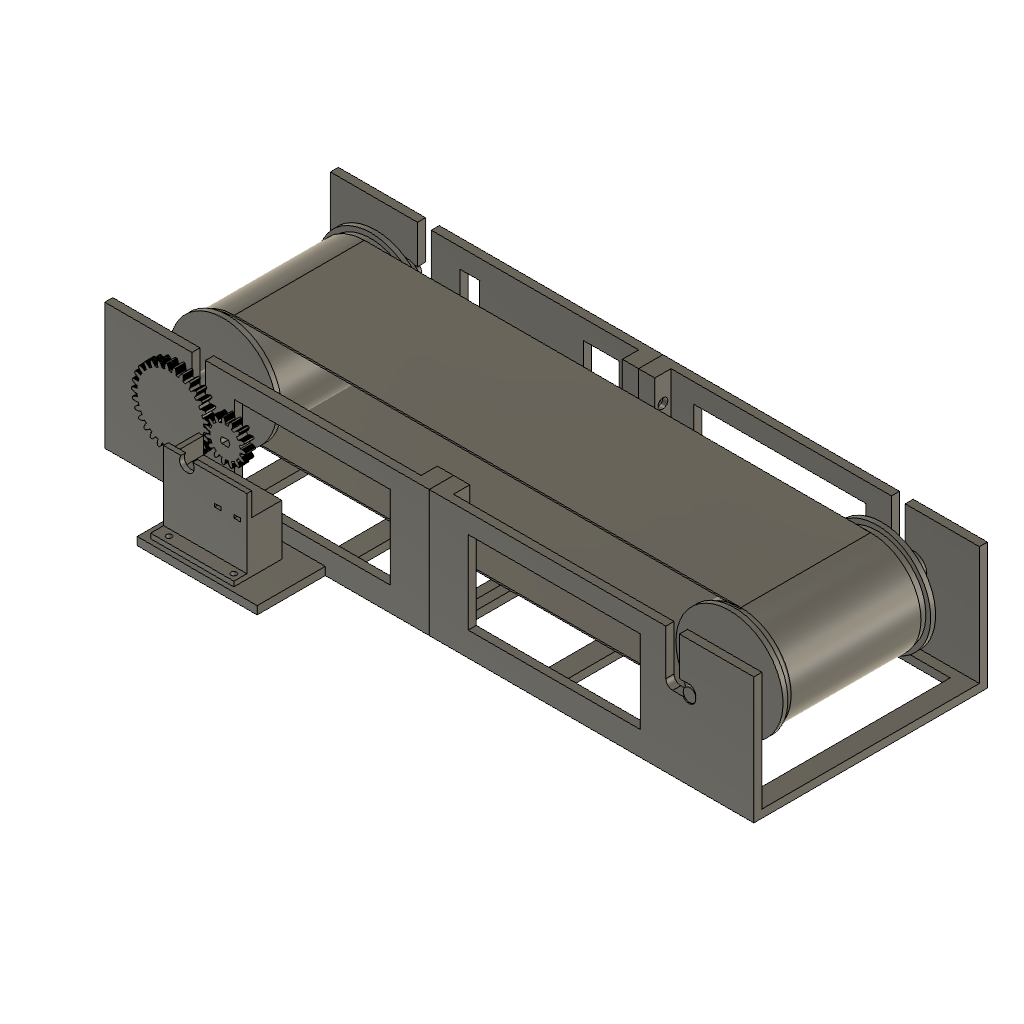
effente_conveyor_2x (Autodesk Fusion 360 design; units mm, degrees)
part number: 2026-11-16-22-43-17-711
part number: 2026-11-16-22-43-17-788
part number: 2026-11-16-22-43-19-483
part number: 2026-11-16-22-43-26-721
part number: 2026-11-16-22-43-27-187
part number: 2026-11-16-22-43-30-080
part number: 2026-11-16-22-43-30-572
Autodesk Fusion 360 part; units mm, degrees
(part 1 of 2)
sketch "Sketch1" plane through (0, 0, 0) normal (0, 0, 1) x (1, 0, 0) in component "Frame"
  line L0 (0, 0) -> (400, 0)
  line L1 (400, 0) -> (400, 144)
  line L2 (400, 144) -> (0, 144)
  line L3 (0, 144) -> (0, 0)
extrude "Extrude1" add sketch "Sketch1" along normal blind 5 makes body 1 in component "Frame"
ref_plane "WorkPlane1" through (0, 0, 5) normal (0, 0, 1) x (1, 0, 0) in component "Frame"
sketch "Sketch2" plane through (0, 0, 5) normal (0, 0, 1) x (1, 0, 0) in component "Frame"
  line L0 (0, 0) -> (400, 0)
  line L1 (400, 0) -> (400, 5)
  line L2 (400, 5) -> (0, 5)
  line L3 (0, 5) -> (0, 0)
extrude "Extrude2" add sketch "Sketch2" along normal blind 73 bodies 1 in component "Frame"
ref_plane "WorkPlane2" through (0, 0, 5) normal (0, 0, 1) x (1, 0, 0) in component "Frame"
sketch "Sketch3" plane through (0, 0, 5) normal (0, 0, 1) x (1, 0, 0) in component "Frame"
  line L0 (0, 139) -> (400, 139)
  line L1 (400, 139) -> (400, 144)
  line L2 (400, 144) -> (0, 144)
  line L3 (0, 144) -> (0, 139)
extrude "Extrude3" add sketch "Sketch3" along normal blind 73 bodies 1 in component "Frame"
sketch "Sketch4" plane through (0, 0, 0) normal (0, 0, 1) x (1, 0, 0) in component "Frame"
  line L0 (62, -42) -> (136, -42)
  line L1 (136, -42) -> (136, 0.5)
  line L2 (136, 0.5) -> (62, 0.5)
  line L3 (62, 0.5) -> (62, -42)
extrude "Extrude4" add sketch "Sketch4" along normal blind 5 bodies 1 in component "Frame"
ref_plane "WorkPlane3" through (0, 2.5, 0) normal (0, 1, 0) x (0, 0, 1) in component "Frame"
sketch "Sketch5" plane through (0, 2.5, 0) normal (0, 1, 0) x (1, 0, 0) in component "Frame"
  line L0 (80, -15) -> (176, -15)
  line L1 (176, -15) -> (176, -66)
  line L2 (176, -66) -> (80, -66)
  line L3 (80, -66) -> (80, -15)
extrude "Extrude5" cut sketch "Sketch5" along normal mid plane 6 bodies 1 in component "Frame"
ref_plane "WorkPlane4" through (0, 2.5, 0) normal (0, 1, 0) x (0, 0, 1) in component "Frame"
sketch "Sketch6" plane through (0, 2.5, 0) normal (0, 1, 0) x (1, 0, 0) in component "Frame"
  line L0 (224, -15) -> (330, -15)
  line L1 (330, -15) -> (330, -66)
  line L2 (330, -66) -> (224, -66)
  line L3 (224, -66) -> (224, -15)
extrude "Extrude6" cut sketch "Sketch6" along normal mid plane 6 bodies 1 in component "Frame"
ref_plane "WorkPlane5" through (0, 141.5, 0) normal (0, 1, 0) x (0, 0, 1) in component "Frame"
sketch "Sketch7" plane through (0, 141.5, 0) normal (0, 1, 0) x (1, 0, 0) in component "Frame"
  line L0 (80, -15) -> (92, -15)
  line L1 (92, -15) -> (92, -66)
  line L2 (92, -66) -> (80, -66)
  line L3 (80, -66) -> (80, -15)
extrude "Extrude7" cut sketch "Sketch7" along normal mid plane 6 bodies 1 in component "Frame"
ref_plane "WorkPlane6" through (0, 141.5, 0) normal (0, 1, 0) x (0, 0, 1) in component "Frame"
sketch "Sketch8" plane through (0, 141.5, 0) normal (0, 1, 0) x (1, 0, 0) in component "Frame"
  line L0 (156, -15) -> (178, -15)
  line L1 (178, -15) -> (178, -66)
  line L2 (178, -66) -> (156, -66)
  line L3 (156, -66) -> (156, -15)
extrude "Extrude8" cut sketch "Sketch8" along normal mid plane 6 bodies 1 in component "Frame"
ref_plane "WorkPlane7" through (0, 141.5, 0) normal (0, 1, 0) x (0, 0, 1) in component "Frame"
sketch "Sketch9" plane through (0, 141.5, 0) normal (0, 1, 0) x (1, 0, 0) in component "Frame"
  line L0 (224, -15) -> (330, -15)
  line L1 (330, -15) -> (330, -66)
  line L2 (330, -66) -> (224, -66)
  line L3 (224, -66) -> (224, -15)
extrude "Extrude9" cut sketch "Sketch9" along normal mid plane 6 bodies 1 in component "Frame"
ref_plane "WorkPlane8" through (0, 0, -0.5) normal (0, 0, 1) x (1, 0, 0) in component "Frame"
sketch "Sketch10" plane through (0, 0, -0.5) normal (0, 0, 1) x (1, 0, 0) in component "Frame"
  line L0 (12, 11) -> (64.6667, 11)
  line L1 (64.6667, 11) -> (64.6667, 133)
  line L2 (64.6667, 133) -> (12, 133)
  line L3 (12, 133) -> (12, 11)
extrude "Extrude10" cut sketch "Sketch10" along normal blind 6 bodies 1 in component "Frame"
ref_plane "WorkPlane9" through (0, 0, -0.5) normal (0, 0, 1) x (1, 0, 0) in component "Frame"
sketch "Sketch11" plane through (0, 0, -0.5) normal (0, 0, 1) x (1, 0, 0) in component "Frame"
  line L0 (76.6667, 11) -> (129.3333, 11)
  line L1 (129.3333, 11) -> (129.3333, 133)
  line L2 (129.3333, 133) -> (76.6667, 133)
  line L3 (76.6667, 133) -> (76.6667, 11)
extrude "Extrude11" cut sketch "Sketch11" along normal blind 6 bodies 1 in component "Frame"
ref_plane "WorkPlane10" through (0, 0, -0.5) normal (0, 0, 1) x (1, 0, 0) in component "Frame"
sketch "Sketch12" plane through (0, 0, -0.5) normal (0, 0, 1) x (1, 0, 0) in component "Frame"
  line L0 (141.3333, 11) -> (194, 11)
  line L1 (194, 11) -> (194, 133)
  line L2 (194, 133) -> (141.3333, 133)
  line L3 (141.3333, 133) -> (141.3333, 11)
extrude "Extrude12" cut sketch "Sketch12" along normal blind 6 bodies 1 in component "Frame"
ref_plane "WorkPlane11" through (0, 0, -0.5) normal (0, 0, 1) x (1, 0, 0) in component "Frame"
sketch "Sketch13" plane through (0, 0, -0.5) normal (0, 0, 1) x (1, 0, 0) in component "Frame"
  line L0 (206, 11) -> (258.6667, 11)
  line L1 (258.6667, 11) -> (258.6667, 133)
  line L2 (258.6667, 133) -> (206, 133)
  line L3 (206, 133) -> (206, 11)
extrude "Extrude13" cut sketch "Sketch13" along normal blind 6 bodies 1 in component "Frame"
ref_plane "WorkPlane12" through (0, 0, -0.5) normal (0, 0, 1) x (1, 0, 0) in component "Frame"
sketch "Sketch14" plane through (0, 0, -0.5) normal (0, 0, 1) x (1, 0, 0) in component "Frame"
  line L0 (270.6667, 11) -> (323.3333, 11)
  line L1 (323.3333, 11) -> (323.3333, 133)
  line L2 (323.3333, 133) -> (270.6667, 133)
  line L3 (270.6667, 133) -> (270.6667, 11)
extrude "Extrude14" cut sketch "Sketch14" along normal blind 6 bodies 1 in component "Frame"
ref_plane "WorkPlane13" through (0, 0, -0.5) normal (0, 0, 1) x (1, 0, 0) in component "Frame"
sketch "Sketch15" plane through (0, 0, -0.5) normal (0, 0, 1) x (1, 0, 0) in component "Frame"
  line L0 (335.3333, 11) -> (388, 11)
  line L1 (388, 11) -> (388, 133)
  line L2 (388, 133) -> (335.3333, 133)
  line L3 (335.3333, 133) -> (335.3333, 11)
extrude "Extrude15" cut sketch "Sketch15" along normal blind 6 bodies 1 in component "Frame"
sketch "Sketch16" plane through (0, 0, 0) normal (0, 0, 1) x (1, 0, 0) in component "Frame"
  line L0 (190, 4.99) -> (210, 4.99)
  line L1 (210, 4.99) -> (210, 15)
  line L2 (210, 15) -> (190, 15)
  line L3 (190, 15) -> (190, 4.99)
extrude "Extrude16" add sketch "Sketch16" along normal blind 78 bodies 1 in component "Frame"
sketch "Sketch17" plane through (0, 0, 0) normal (0, 0, 1) x (1, 0, 0) in component "Frame"
  line L0 (190, 129) -> (210, 129)
  line L1 (210, 129) -> (210, 139.01)
  line L2 (210, 139.01) -> (190, 139.01)
  line L3 (190, 139.01) -> (190, 129)
extrude "Extrude17" add sketch "Sketch17" along normal blind 78 bodies 1 in component "Frame"
sketch "Sketch18" plane through (0, 0, 0) normal (0, 0, 1) x (1, 0, 0) in component "Frame"
  line L0 (190, 60) -> (210, 60)
  line L1 (210, 60) -> (210, 84)
  line L2 (210, 84) -> (190, 84)
  line L3 (190, 84) -> (190, 60)
extrude "Extrude18" add sketch "Sketch18" along normal blind 13 bodies 1 in component "Frame"
ref_plane "WorkPlane14" through (200, 0, 0) normal (1, 0, 0) x (0, 1, 0) in component "Frame"
sketch "Sketch19" plane through (200, 0, 0) normal (1, 0, 0) x (0, 0, -1) in component "Frame"
  circle A0 centre (-22, 10) radius 1.7
extrude "Extrude19" cut sketch "Sketch19" along normal mid plane 21 bodies 1 in component "Frame"
ref_plane "WorkPlane15" through (191, 0, 0) normal (1, 0, 0) x (0, 1, 0) in component "Frame"
sketch "Sketch20" plane through (191, 0, 0) normal (1, 0, 0) x (0, 0, -1) in component "Frame"
  line L0 (-23.6166, 12.8) -> (-25.2332, 10)
  line L1 (-25.2332, 10) -> (-23.6166, 7.2)
  line L2 (-23.6166, 7.2) -> (-20.3834, 7.2)
  line L3 (-20.3834, 7.2) -> (-18.7668, 10)
  line L4 (-18.7668, 10) -> (-20.3834, 12.8)
  line L5 (-20.3834, 12.8) -> (-23.6166, 12.8)
extrude "Extrude20" cut sketch "Sketch20" along normal mid plane 3 bodies 1 in component "Frame"
ref_plane "WorkPlane16" through (208.75, 0, 0) normal (1, 0, 0) x (0, 1, 0) in component "Frame"
sketch "Sketch21" plane through (208.75, 0, 0) normal (1, 0, 0) x (0, 0, -1) in component "Frame"
  circle A0 centre (-22, 10) radius 3
extrude "Extrude21" cut sketch "Sketch21" along normal mid plane 3.5 bodies 1 in component "Frame"
ref_plane "WorkPlane17" through (200, 0, 0) normal (1, 0, 0) x (0, 1, 0) in component "Frame"
sketch "Sketch22" plane through (200, 0, 0) normal (1, 0, 0) x (0, 0, -1) in component "Frame"
  circle A0 centre (-62, 10) radius 1.7
extrude "Extrude22" cut sketch "Sketch22" along normal mid plane 21 bodies 1 in component "Frame"
ref_plane "WorkPlane18" through (191, 0, 0) normal (1, 0, 0) x (0, 1, 0) in component "Frame"
sketch "Sketch23" plane through (191, 0, 0) normal (1, 0, 0) x (0, 0, -1) in component "Frame"
  line L0 (-63.6166, 12.8) -> (-65.2332, 10)
  line L1 (-65.2332, 10) -> (-63.6166, 7.2)
  line L2 (-63.6166, 7.2) -> (-60.3834, 7.2)
  line L3 (-60.3834, 7.2) -> (-58.7668, 10)
  line L4 (-58.7668, 10) -> (-60.3834, 12.8)
  line L5 (-60.3834, 12.8) -> (-63.6166, 12.8)
extrude "Extrude23" cut sketch "Sketch23" along normal mid plane 3 bodies 1 in component "Frame"
ref_plane "WorkPlane19" through (208.75, 0, 0) normal (1, 0, 0) x (0, 1, 0) in component "Frame"
sketch "Sketch24" plane through (208.75, 0, 0) normal (1, 0, 0) x (0, 0, -1) in component "Frame"
  circle A0 centre (-62, 10) radius 3
extrude "Extrude24" cut sketch "Sketch24" along normal mid plane 3.5 bodies 1 in component "Frame"
ref_plane "WorkPlane20" through (200, 0, 0) normal (1, 0, 0) x (0, 1, 0) in component "Frame"
sketch "Sketch25" plane through (200, 0, 0) normal (1, 0, 0) x (0, 0, -1) in component "Frame"
  circle A0 centre (-22, 134) radius 1.7
extrude "Extrude25" cut sketch "Sketch25" along normal mid plane 21 bodies 1 in component "Frame"
ref_plane "WorkPlane21" through (191, 0, 0) normal (1, 0, 0) x (0, 1, 0) in component "Frame"
sketch "Sketch26" plane through (191, 0, 0) normal (1, 0, 0) x (0, 0, -1) in component "Frame"
  line L0 (-23.6166, 136.8) -> (-25.2332, 134)
  line L1 (-25.2332, 134) -> (-23.6166, 131.2)
  line L2 (-23.6166, 131.2) -> (-20.3834, 131.2)
  line L3 (-20.3834, 131.2) -> (-18.7668, 134)
  line L4 (-18.7668, 134) -> (-20.3834, 136.8)
  line L5 (-20.3834, 136.8) -> (-23.6166, 136.8)
extrude "Extrude26" cut sketch "Sketch26" along normal mid plane 3 bodies 1 in component "Frame"
ref_plane "WorkPlane22" through (208.75, 0, 0) normal (1, 0, 0) x (0, 1, 0) in component "Frame"
sketch "Sketch27" plane through (208.75, 0, 0) normal (1, 0, 0) x (0, 0, -1) in component "Frame"
  circle A0 centre (-22, 134) radius 3
extrude "Extrude27" cut sketch "Sketch27" along normal mid plane 3.5 bodies 1 in component "Frame"
ref_plane "WorkPlane23" through (200, 0, 0) normal (1, 0, 0) x (0, 1, 0) in component "Frame"
sketch "Sketch28" plane through (200, 0, 0) normal (1, 0, 0) x (0, 0, -1) in component "Frame"
  circle A0 centre (-62, 134) radius 1.7
extrude "Extrude28" cut sketch "Sketch28" along normal mid plane 21 bodies 1 in component "Frame"
ref_plane "WorkPlane24" through (191, 0, 0) normal (1, 0, 0) x (0, 1, 0) in component "Frame"
sketch "Sketch29" plane through (191, 0, 0) normal (1, 0, 0) x (0, 0, -1) in component "Frame"
  line L0 (-63.6166, 136.8) -> (-65.2332, 134)
  line L1 (-65.2332, 134) -> (-63.6166, 131.2)
  line L2 (-63.6166, 131.2) -> (-60.3834, 131.2)
  line L3 (-60.3834, 131.2) -> (-58.7668, 134)
  line L4 (-58.7668, 134) -> (-60.3834, 136.8)
  line L5 (-60.3834, 136.8) -> (-63.6166, 136.8)
extrude "Extrude29" cut sketch "Sketch29" along normal mid plane 3 bodies 1 in component "Frame"
ref_plane "WorkPlane25" through (208.75, 0, 0) normal (1, 0, 0) x (0, 1, 0) in component "Frame"
sketch "Sketch30" plane through (208.75, 0, 0) normal (1, 0, 0) x (0, 0, -1) in component "Frame"
  circle A0 centre (-62, 134) radius 3
extrude "Extrude30" cut sketch "Sketch30" along normal mid plane 3.5 bodies 1 in component "Frame"
ref_plane "WorkPlane26" through (200, 0, 0) normal (1, 0, 0) x (0, 1, 0) in component "Frame"
sketch "Sketch31" plane through (200, 0, 0) normal (1, 0, 0) x (0, 0, -1) in component "Frame"
  circle A0 centre (-8, 72) radius 1.7
extrude "Extrude31" cut sketch "Sketch31" along normal mid plane 21 bodies 1 in component "Frame"
ref_plane "WorkPlane27" through (191, 0, 0) normal (1, 0, 0) x (0, 1, 0) in component "Frame"
sketch "Sketch32" plane through (191, 0, 0) normal (1, 0, 0) x (0, 0, -1) in component "Frame"
  line L0 (-9.6166, 74.8) -> (-11.2332, 72)
  line L1 (-11.2332, 72) -> (-9.6166, 69.2)
  line L2 (-9.6166, 69.2) -> (-6.3834, 69.2)
  line L3 (-6.3834, 69.2) -> (-4.7668, 72)
  line L4 (-4.7668, 72) -> (-6.3834, 74.8)
  line L5 (-6.3834, 74.8) -> (-9.6166, 74.8)
extrude "Extrude32" cut sketch "Sketch32" along normal mid plane 3 bodies 1 in component "Frame"
ref_plane "WorkPlane28" through (208.75, 0, 0) normal (1, 0, 0) x (0, 1, 0) in component "Frame"
sketch "Sketch33" plane through (208.75, 0, 0) normal (1, 0, 0) x (0, 0, -1) in component "Frame"
  circle A0 centre (-8, 72) radius 3
extrude "Extrude33" cut sketch "Sketch33" along normal mid plane 3.5 bodies 1 in component "Frame"
ref_plane "WorkPlane29" through (0, 2.5, 0) normal (0, 1, 0) x (0, 0, 1) in component "Frame"
sketch "Sketch34" plane through (0, 2.5, 0) normal (0, 1, 0) x (1, 0, 0) in component "Frame"
  circle A0 centre (48, -48) radius 4.2
extrude "Extrude34" cut sketch "Sketch34" along normal mid plane 6 bodies 1 in component "Frame"
ref_plane "WorkPlane30" through (0, 2.5, 0) normal (0, 1, 0) x (0, 0, 1) in component "Frame"
sketch "Sketch35" plane through (0, 2.5, 0) normal (0, 1, 0) x (1, 0, 0) in component "Frame"
  line L0 (48, -45.8) -> (58, -45.8)
  line L1 (58, -45.8) -> (58, -54.2)
  line L2 (58, -54.2) -> (48, -54.2)
  line L3 (48, -54.2) -> (48, -45.8)
extrude "Extrude35" cut sketch "Sketch35" along normal mid plane 6 bodies 1 in component "Frame"
ref_plane "WorkPlane31" through (0, 2.5, 0) normal (0, 1, 0) x (0, 0, 1) in component "Frame"
sketch "Sketch36" plane through (0, 2.5, 0) normal (0, 1, 0) x (1, 0, 0) in component "Frame"
  circle A0 centre (48, -50) radius 4.2
extrude "Extrude36" cut sketch "Sketch36" along normal mid plane 6 bodies 1 in component "Frame"
ref_plane "WorkPlane32" through (0, 2.5, 0) normal (0, 1, 0) x (0, 0, 1) in component "Frame"
sketch "Sketch37" plane through (0, 2.5, 0) normal (0, 1, 0) x (1, 0, 0) in component "Frame"
  circle A0 centre (58, -50) radius 4.2
extrude "Extrude37" cut sketch "Sketch37" along normal mid plane 6 bodies 1 in component "Frame"
ref_plane "WorkPlane33" through (0, 2.5, 0) normal (0, 1, 0) x (0, 0, 1) in component "Frame"
sketch "Sketch38" plane through (0, 2.5, 0) normal (0, 1, 0) x (1, 0, 0) in component "Frame"
  line L0 (53.8, -50) -> (62.2, -50)
  line L1 (62.2, -50) -> (62.2, -79)
  line L2 (62.2, -79) -> (53.8, -79)
  line L3 (53.8, -79) -> (53.8, -50)
extrude "Extrude38" cut sketch "Sketch38" along normal mid plane 6 bodies 1 in component "Frame"
ref_plane "WorkPlane34" through (0, 141.5, 0) normal (0, 1, 0) x (0, 0, 1) in component "Frame"
sketch "Sketch39" plane through (0, 141.5, 0) normal (0, 1, 0) x (1, 0, 0) in component "Frame"
  circle A0 centre (48, -48) radius 4.2
extrude "Extrude39" cut sketch "Sketch39" along normal mid plane 6 bodies 1 in component "Frame"
ref_plane "WorkPlane35" through (0, 141.5, 0) normal (0, 1, 0) x (0, 0, 1) in component "Frame"
sketch "Sketch40" plane through (0, 141.5, 0) normal (0, 1, 0) x (1, 0, 0) in component "Frame"
  line L0 (48, -45.8) -> (58, -45.8)
  line L1 (58, -45.8) -> (58, -54.2)
  line L2 (58, -54.2) -> (48, -54.2)
  line L3 (48, -54.2) -> (48, -45.8)
extrude "Extrude40" cut sketch "Sketch40" along normal mid plane 6 bodies 1 in component "Frame"
ref_plane "WorkPlane36" through (0, 141.5, 0) normal (0, 1, 0) x (0, 0, 1) in component "Frame"
sketch "Sketch41" plane through (0, 141.5, 0) normal (0, 1, 0) x (1, 0, 0) in component "Frame"
  circle A0 centre (48, -50) radius 4.2
extrude "Extrude41" cut sketch "Sketch41" along normal mid plane 6 bodies 1 in component "Frame"
ref_plane "WorkPlane37" through (0, 141.5, 0) normal (0, 1, 0) x (0, 0, 1) in component "Frame"
sketch "Sketch42" plane through (0, 141.5, 0) normal (0, 1, 0) x (1, 0, 0) in component "Frame"
  circle A0 centre (58, -50) radius 4.2
extrude "Extrude42" cut sketch "Sketch42" along normal mid plane 6 bodies 1 in component "Frame"
ref_plane "WorkPlane38" through (0, 141.5, 0) normal (0, 1, 0) x (0, 0, 1) in component "Frame"
sketch "Sketch43" plane through (0, 141.5, 0) normal (0, 1, 0) x (1, 0, 0) in component "Frame"
  line L0 (53.8, -50) -> (62.2, -50)
  line L1 (62.2, -50) -> (62.2, -79)
  line L2 (62.2, -79) -> (53.8, -79)
  line L3 (53.8, -79) -> (53.8, -50)
extrude "Extrude43" cut sketch "Sketch43" along normal mid plane 6 bodies 1 in component "Frame"
ref_plane "WorkPlane39" through (0, 2.5, 0) normal (0, 1, 0) x (0, 0, 1) in component "Frame"
sketch "Sketch44" plane through (0, 2.5, 0) normal (0, 1, 0) x (1, 0, 0) in component "Frame"
  circle A0 centre (360, -48) radius 4.2
extrude "Extrude44" cut sketch "Sketch44" along normal mid plane 6 bodies 1 in component "Frame"
ref_plane "WorkPlane40" through (0, 2.5, 0) normal (0, 1, 0) x (0, 0, 1) in component "Frame"
sketch "Sketch45" plane through (0, 2.5, 0) normal (0, 1, 0) x (1, 0, 0) in component "Frame"
  line L0 (350, -45.8) -> (360, -45.8)
  line L1 (360, -45.8) -> (360, -54.2)
  line L2 (360, -54.2) -> (350, -54.2)
  line L3 (350, -54.2) -> (350, -45.8)
extrude "Extrude45" cut sketch "Sketch45" along normal mid plane 6 bodies 1 in component "Frame"
ref_plane "WorkPlane41" through (0, 2.5, 0) normal (0, 1, 0) x (0, 0, 1) in component "Frame"
sketch "Sketch46" plane through (0, 2.5, 0) normal (0, 1, 0) x (1, 0, 0) in component "Frame"
  circle A0 centre (360, -50) radius 4.2
extrude "Extrude46" cut sketch "Sketch46" along normal mid plane 6 bodies 1 in component "Frame"
ref_plane "WorkPlane42" through (0, 2.5, 0) normal (0, 1, 0) x (0, 0, 1) in component "Frame"
sketch "Sketch47" plane through (0, 2.5, 0) normal (0, 1, 0) x (1, 0, 0) in component "Frame"
  circle A0 centre (350, -50) radius 4.2
extrude "Extrude47" cut sketch "Sketch47" along normal mid plane 6 bodies 1 in component "Frame"
ref_plane "WorkPlane43" through (0, 2.5, 0) normal (0, 1, 0) x (0, 0, 1) in component "Frame"
sketch "Sketch48" plane through (0, 2.5, 0) normal (0, 1, 0) x (1, 0, 0) in component "Frame"
  line L0 (345.8, -50) -> (354.2, -50)
  line L1 (354.2, -50) -> (354.2, -79)
  line L2 (354.2, -79) -> (345.8, -79)
  line L3 (345.8, -79) -> (345.8, -50)
extrude "Extrude48" cut sketch "Sketch48" along normal mid plane 6 bodies 1 in component "Frame"
ref_plane "WorkPlane44" through (0, 141.5, 0) normal (0, 1, 0) x (0, 0, 1) in component "Frame"
sketch "Sketch49" plane through (0, 141.5, 0) normal (0, 1, 0) x (1, 0, 0) in component "Frame"
  circle A0 centre (360, -48) radius 4.2
extrude "Extrude49" cut sketch "Sketch49" along normal mid plane 6 bodies 1 in component "Frame"
ref_plane "WorkPlane45" through (0, 141.5, 0) normal (0, 1, 0) x (0, 0, 1) in component "Frame"
sketch "Sketch50" plane through (0, 141.5, 0) normal (0, 1, 0) x (1, 0, 0) in component "Frame"
  line L0 (350, -45.8) -> (360, -45.8)
  line L1 (360, -45.8) -> (360, -54.2)
  line L2 (360, -54.2) -> (350, -54.2)
  line L3 (350, -54.2) -> (350, -45.8)
extrude "Extrude50" cut sketch "Sketch50" along normal mid plane 6 bodies 1 in component "Frame"
ref_plane "WorkPlane46" through (0, 141.5, 0) normal (0, 1, 0) x (0, 0, 1) in component "Frame"
sketch "Sketch51" plane through (0, 141.5, 0) normal (0, 1, 0) x (1, 0, 0) in component "Frame"
  circle A0 centre (360, -50) radius 4.2
extrude "Extrude51" cut sketch "Sketch51" along normal mid plane 6 bodies 1 in component "Frame"
ref_plane "WorkPlane47" through (0, 141.5, 0) normal (0, 1, 0) x (0, 0, 1) in component "Frame"
sketch "Sketch52" plane through (0, 141.5, 0) normal (0, 1, 0) x (1, 0, 0) in component "Frame"
  circle A0 centre (350, -50) radius 4.2
extrude "Extrude52" cut sketch "Sketch52" along normal mid plane 6 bodies 1 in component "Frame"
ref_plane "WorkPlane48" through (0, 141.5, 0) normal (0, 1, 0) x (0, 0, 1) in component "Frame"
sketch "Sketch53" plane through (0, 141.5, 0) normal (0, 1, 0) x (1, 0, 0) in component "Frame"
  line L0 (345.8, -50) -> (354.2, -50)
  line L1 (354.2, -50) -> (354.2, -79)
  line L2 (354.2, -79) -> (345.8, -79)
  line L3 (345.8, -79) -> (345.8, -50)
extrude "Extrude53" cut sketch "Sketch53" along normal mid plane 6 bodies 1 in component "Frame"
ref_plane "WorkPlane49" through (0, 0, -0.5) normal (0, 0, 1) x (1, 0, 0) in component "Frame"
sketch "Sketch54" plane through (0, 0, -0.5) normal (0, 0, 1) x (1, 0, 0) in component "Frame"
  circle A0 centre (74.75, -35.1) radius 1.7
extrude "Extrude54" cut sketch "Sketch54" along normal blind 6 bodies 1 in component "Frame"
ref_plane "WorkPlane50" through (0, 0, -0.5) normal (0, 0, 1) x (1, 0, 0) in component "Frame"
sketch "Sketch55" plane through (0, 0, -0.5) normal (0, 0, 1) x (1, 0, 0) in component "Frame"
  line L0 (77.9832, -35.1) -> (76.3666, -32.3)
  line L1 (76.3666, -32.3) -> (73.1334, -32.3)
  line L2 (73.1334, -32.3) -> (71.5168, -35.1)
  line L3 (71.5168, -35.1) -> (73.1334, -37.9)
  line L4 (73.1334, -37.9) -> (76.3666, -37.9)
  line L5 (76.3666, -37.9) -> (77.9832, -35.1)
extrude "Extrude55" cut sketch "Sketch55" along normal blind 3 bodies 1 in component "Frame"
ref_plane "WorkPlane51" through (0, 0, -0.5) normal (0, 0, 1) x (1, 0, 0) in component "Frame"
sketch "Sketch56" plane through (0, 0, -0.5) normal (0, 0, 1) x (1, 0, 0) in component "Frame"
  circle A0 centre (114.75, -35.1) radius 1.7
extrude "Extrude56" cut sketch "Sketch56" along normal blind 6 bodies 1 in component "Frame"
ref_plane "WorkPlane52" through (0, 0, -0.5) normal (0, 0, 1) x (1, 0, 0) in component "Frame"
sketch "Sketch57" plane through (0, 0, -0.5) normal (0, 0, 1) x (1, 0, 0) in component "Frame"
  line L0 (117.9832, -35.1) -> (116.3666, -32.3)
  line L1 (116.3666, -32.3) -> (113.1334, -32.3)
  line L2 (113.1334, -32.3) -> (111.5168, -35.1)
  line L3 (111.5168, -35.1) -> (113.1334, -37.9)
  line L4 (113.1334, -37.9) -> (116.3666, -37.9)
  line L5 (116.3666, -37.9) -> (117.9832, -35.1)
extrude "Extrude57" cut sketch "Sketch57" along normal blind 3 bodies 1 in component "Frame"
ref_plane "WorkPlane53" through (0, 143.25, 0) normal (0, 1, 0) x (0, 0, 1) in component "Frame"
sketch "Sketch58" plane through (0, 143.25, 0) normal (0, 1, 0) x (1, 0, 0) in component "Frame"
  circle A0 centre (120, -48) radius 10.05
extrude "Extrude58" cut sketch "Sketch58" along normal mid plane 2.5 bodies 1 in component "Frame"
ref_plane "WorkPlane54" through (200, 0, 0) normal (1, 0, 0) x (0, 1, 0) in component "Frame"
split "Split1" by plane through (200, 0, 0) normal (1, 0, 0) bodies 1 makes body 2 at (388.0369, 0, 41.7129) in component "Frame"
ref_plane "WorkPlane1" through (0, 72, 0) normal (0, 1, 0) x (0, 0, 1) in component "Drive roller"
sketch "Sketch1 (2)" plane through (0, 72, 0) normal (0, 1, 0) x (1, 0, 0) in component "Drive roller"
  circle A0 centre (48, -48) radius 30
extrude "Extrude1'" add sketch "Sketch1 (2)" along normal mid plane 88 separate body makes body 3 in component "Drive roller"
ref_plane "WorkPlane2" through (0, 26.5, 0) normal (0, 1, 0) x (0, 0, 1) in component "Drive roller"
sketch "Sketch2 (2)" plane through (0, 26.5, 0) normal (0, 1, 0) x (1, 0, 0) in component "Drive roller"
  circle A0 centre (48, -48) radius 33
extrude "Extrude2'" add sketch "Sketch2 (2)" along normal mid plane 3 bodies 3 in component "Drive roller"
ref_plane "WorkPlane3" through (0, 117.5, 0) normal (0, 1, 0) x (0, 0, 1) in component "Drive roller"
sketch "Sketch3 (2)" plane through (0, 117.5, 0) normal (0, 1, 0) x (1, 0, 0) in component "Drive roller"
  circle A0 centre (48, -48) radius 33
extrude "Extrude3'" add sketch "Sketch3 (2)" along normal mid plane 3 bodies 3 in component "Drive roller"
ref_plane "WorkPlane4" through (0, 128.75, 0) normal (0, 1, 0) x (0, 0, 1) in component "Drive roller"
sketch "Sketch4 (2)" plane through (0, 128.75, 0) normal (0, 1, 0) x (1, 0, 0) in component "Drive roller"
  circle A0 centre (48, -48) radius 8
extrude "Extrude4'" add sketch "Sketch4 (2)" along normal mid plane 19.5 bodies 3 in component "Drive roller"
ref_plane "WorkPlane5" through (0, 141, 0) normal (0, 1, 0) x (0, 0, 1) in component "Drive roller"
sketch "Sketch5 (2)" plane through (0, 141, 0) normal (0, 1, 0) x (1, 0, 0) in component "Drive roller"
  circle A0 centre (48, -48) radius 4
extrude "Extrude5'" add sketch "Sketch5 (2)" along normal mid plane 5 bodies 3 in component "Drive roller"
ref_plane "WorkPlane6" through (0, 15.25, 0) normal (0, 1, 0) x (0, 0, 1) in component "Drive roller"
sketch "Sketch6 (2)" plane through (0, 15.25, 0) normal (0, 1, 0) x (1, 0, 0) in component "Drive roller"
  circle A0 centre (48, -48) radius 8
extrude "Extrude6'" add sketch "Sketch6 (2)" along normal mid plane 19.5 bodies 3 in component "Drive roller"
ref_plane "WorkPlane7" through (0, 1.995, 0) normal (0, 1, 0) x (0, 0, 1) in component "Drive roller"
sketch "Sketch7 (2)" plane through (0, 1.995, 0) normal (0, 1, 0) x (1, 0, 0) in component "Drive roller"
  circle A0 centre (48, -48) radius 4
extrude "Extrude7'" add sketch "Sketch7 (2)" along normal mid plane 7.01 bodies 3 in component "Drive roller"
ref_plane "WorkPlane8" through (0, -4.5, 0) normal (0, 1, 0) x (0, 0, 1) in component "Drive roller"
sketch "Sketch8 (2)" plane through (0, -4.5, 0) normal (0, 1, 0) x (1, 0, 0) in component "Drive roller"
  line L0 (68.5814, -46.6595) -> (69.0984, -46.6258)
  line L1 (69.0984, -46.6258) -> (69.4576, -46.6466)
  line L2 (69.4576, -46.6466) -> (69.8189, -46.7052)
  line L3 (69.8189, -46.7052) -> (70.1814, -46.7894)
  line L4 (70.1814, -46.7894) -> (70.5445, -46.8952)
  line L5 (70.5445, -46.8952) -> (70.9077, -47.0204)
  line L6 (70.9077, -47.0204) -> (71.2707, -47.1637)
  line L7 (71.2707, -47.1637) -> (71.6332, -47.3239)
  line L8 (71.6332, -47.3239) -> (71.9948, -47.5003)
  line L9 (71.9948, -47.5003) -> (71.9948, -48.4997)
  line L10 (71.9948, -48.4997) -> (71.6332, -48.6761)
  line L11 (71.6332, -48.6761) -> (71.2707, -48.8363)
  line L12 (71.2707, -48.8363) -> (70.9077, -48.9796)
  line L13 (70.9077, -48.9796) -> (70.5445, -49.1048)
  line L14 (70.5445, -49.1048) -> (70.1814, -49.2106)
  line L15 (70.1814, -49.2106) -> (69.8189, -49.2948)
  line L16 (69.8189, -49.2948) -> (69.4576, -49.3534)
  line L17 (69.4576, -49.3534) -> (69.0984, -49.3742)
  line L18 (69.0984, -49.3742) -> (68.5814, -49.3405)
  line L19 (68.5814, -49.3405) -> (68.4104, -50.9679)
  line L20 (68.4104, -50.9679) -> (68.923, -51.0424)
  line L21 (68.923, -51.0424) -> (69.27, -51.1375)
  line L22 (69.27, -51.1375) -> (69.6113, -51.2699)
  line L23 (69.6113, -51.2699) -> (69.9484, -51.4276)
  line L24 (69.9484, -51.4276) -> (70.2815, -51.6066)
  line L25 (70.2815, -51.6066) -> (70.6108, -51.8046)
  line L26 (70.6108, -51.8046) -> (70.9361, -52.0202)
  line L27 (70.9361, -52.0202) -> (71.2573, -52.2523)
  line L28 (71.2573, -52.2523) -> (71.5743, -52.5)
  line L29 (71.5743, -52.5) -> (71.3666, -53.4776)
  line L30 (71.3666, -53.4776) -> (70.9762, -53.575)
  line L31 (70.9762, -53.575) -> (70.5883, -53.6563)
  line L32 (70.5883, -53.6563) -> (70.2035, -53.7209)
  line L33 (70.2035, -53.7209) -> (69.8221, -53.7679)
  line L34 (69.8221, -53.7679) -> (69.445, -53.796)
  line L35 (69.445, -53.796) -> (69.0729, -53.803)
  line L36 (69.0729, -53.803) -> (68.7073, -53.7851)
  line L37 (68.7073, -53.7851) -> (68.3516, -53.7308)
  line L38 (68.3516, -53.7308) -> (67.8529, -53.5904)
  line L39 (67.8529, -53.5904) -> (67.3473, -55.1466)
  line L40 (67.3473, -55.1466) -> (67.8333, -55.3261)
  line L41 (67.8333, -55.3261) -> (68.1529, -55.4912)
  line L42 (68.1529, -55.4912) -> (68.4592, -55.6917)
  line L43 (68.4592, -55.6917) -> (68.7561, -55.916)
  line L44 (68.7561, -55.916) -> (69.0448, -56.1604)
  line L45 (69.0448, -56.1604) -> (69.3257, -56.4225)
  line L46 (69.3257, -56.4225) -> (69.599, -56.701)
  line L47 (69.599, -56.701) -> (69.865, -56.9948)
  line L48 (69.865, -56.9948) -> (70.1236, -57.3031)
  line L49 (70.1236, -57.3031) -> (69.7171, -58.216)
  line L50 (69.7171, -58.216) -> (69.315, -58.2302)
  line L51 (69.315, -58.2302) -> (68.9187, -58.2291)
  line L52 (68.9187, -58.2291) -> (68.5288, -58.2123)
  line L53 (68.5288, -58.2123) -> (68.146, -58.179)
  line L54 (68.146, -58.179) -> (67.7713, -58.128)
  line L55 (67.7713, -58.128) -> (67.4059, -58.0575)
  line L56 (67.4059, -58.0575) -> (67.052, -57.9639)
  line L57 (67.052, -57.9639) -> (66.7154, -57.8369)
  line L58 (66.7154, -57.8369) -> (66.2568, -57.5959)
  line L59 (66.2568, -57.5959) -> (65.4386, -59.0129)
  line L60 (65.4386, -59.0129) -> (65.8767, -59.2895)
  line L61 (65.8767, -59.2895) -> (66.155, -59.5175)
  line L62 (66.155, -59.5175) -> (66.413, -59.7773)
  line L63 (66.413, -59.7773) -> (66.6567, -60.0585)
  line L64 (66.6567, -60.0585) -> (66.8883, -60.3575)
  line L65 (66.8883, -60.3575) -> (67.1085, -60.6723)
  line L66 (67.1085, -60.6723) -> (67.318, -61.0016)
  line L67 (67.318, -61.0016) -> (67.5171, -61.3443)
  line L68 (67.5171, -61.3443) -> (67.7059, -61.6995)
  line L69 (67.7059, -61.6995) -> (67.1185, -62.508)
  line L70 (67.1185, -62.508) -> (66.7223, -62.4382)
  line L71 (66.7223, -62.4382) -> (66.3349, -62.3548)
  line L72 (66.3349, -62.3548) -> (65.957, -62.2573)
  line L73 (65.957, -62.2573) -> (65.5895, -62.1451)
  line L74 (65.5895, -62.1451) -> (65.2335, -62.0173)
  line L75 (65.2335, -62.0173) -> (64.8908, -61.8724)
  line L76 (64.8908, -61.8724) -> (64.564, -61.7073)
  line L77 (64.564, -61.7073) -> (64.2612, -61.5131)
  line L78 (64.2612, -61.5131) -> (63.8627, -61.182)
  line L79 (63.8627, -61.182) -> (62.7679, -62.398)
  line L80 (62.7679, -62.398) -> (63.1388, -62.7596)
  line L81 (63.1388, -62.7596) -> (63.3637, -63.0405)
  line L82 (63.3637, -63.0405) -> (63.562, -63.3482)
  line L83 (63.562, -63.3482) -> (63.7419, -63.6739)
  line L84 (63.7419, -63.6739) -> (63.9062, -64.0146)
  line L85 (63.9062, -64.0146) -> (64.0562, -64.3683)
  line L86 (64.0562, -64.3683) -> (64.1927, -64.7339)
  line L87 (64.1927, -64.7339) -> (64.3162, -65.1105)
  line L88 (64.3162, -65.1105) -> (64.427, -65.4973)
  line L89 (64.427, -65.4973) -> (63.6843, -66.166)
  line L90 (63.6843, -66.166) -> (63.3113, -66.0153)
  line L91 (63.3113, -66.0153) -> (62.9497, -65.8531)
  line L92 (62.9497, -65.8531) -> (62.6003, -65.6792)
  line L93 (62.6003, -65.6792) -> (62.2642, -65.4931)
  line L94 (62.2642, -65.4931) -> (61.9426, -65.2941)
  line L95 (61.9426, -65.2941) -> (61.6375, -65.081)
  line L96 (61.6375, -65.081) -> (61.3522, -64.8517)
  line L97 (61.3522, -64.8517) -> (61.0963, -64.5987)
  line L98 (61.0963, -64.5987) -> (60.7754, -64.192)
  line L99 (60.7754, -64.192) -> (59.4516, -65.1537)
  line L100 (59.4516, -65.1537) -> (59.7393, -65.5846)
  line L101 (59.7393, -65.5846) -> (59.9008, -65.9061)
  line L102 (59.9008, -65.9061) -> (60.0308, -66.2483)
  line L103 (60.0308, -66.2483) -> (60.1392, -66.6043)
  line L104 (60.1392, -66.6043) -> (60.229, -66.9717)
  line L105 (60.229, -66.9717) -> (60.3022, -67.3489)
  line L106 (60.3022, -67.3489) -> (60.3597, -67.7349)
  line L107 (60.3597, -67.7349) -> (60.4021, -68.1289)
  line L108 (60.4021, -68.1289) -> (60.4301, -68.5303)
  line L109 (60.4301, -68.5303) -> (59.5647, -69.0299)
  line L110 (59.5647, -69.0299) -> (59.2311, -68.805)
  line L111 (59.2311, -68.805) -> (58.9111, -68.5712)
  line L112 (58.9111, -68.5712) -> (58.6055, -68.3284)
  line L113 (58.6055, -68.3284) -> (58.3154, -68.0765)
  line L114 (58.3154, -68.0765) -> (58.0423, -67.815)
  line L115 (58.0423, -67.815) -> (57.7881, -67.5432)
  line L116 (57.7881, -67.5432) -> (57.5567, -67.2595)
  line L117 (57.5567, -67.2595) -> (57.3591, -66.9588)
  line L118 (57.3591, -66.9588) -> (57.1297, -66.4943)
  line L119 (57.1297, -66.4943) -> (55.6349, -67.1598)
  line L120 (55.6349, -67.1598) -> (55.8267, -67.6411)
  line L121 (55.8267, -67.6411) -> (55.9179, -67.9891)
  line L122 (55.9179, -67.9891) -> (55.9739, -68.3509)
  line L123 (55.9739, -68.3509) -> (56.0058, -68.7217)
  line L124 (56.0058, -68.7217) -> (56.0174, -69.0997)
  line L125 (56.0174, -69.0997) -> (56.0105, -69.4838)
  line L126 (56.0105, -69.4838) -> (55.9864, -69.8734)
  line L127 (55.9864, -69.8734) -> (55.9461, -70.2676)
  line L128 (55.9461, -70.2676) -> (55.89, -70.666)
  line L129 (55.89, -70.666) -> (54.9396, -70.9748)
  line L130 (54.9396, -70.9748) -> (54.66, -70.6855)
  line L131 (54.66, -70.6855) -> (54.3957, -70.3902)
  line L132 (54.3957, -70.3902) -> (54.1473, -70.0892)
  line L133 (54.1473, -70.0892) -> (53.9159, -69.7825)
  line L134 (53.9159, -69.7825) -> (53.703, -69.4699)
  line L135 (53.703, -69.4699) -> (53.511, -69.1512)
  line L136 (53.511, -69.1512) -> (53.3436, -68.8256)
  line L137 (53.3436, -68.8256) -> (53.2128, -68.4904)
  line L138 (53.2128, -68.4904) -> (53.0851, -67.9883)
  line L139 (53.0851, -67.9883) -> (51.4845, -68.3285)
  line L140 (51.4845, -68.3285) -> (51.5721, -68.8392)
  line L141 (51.5721, -68.8392) -> (51.5889, -69.1986)
  line L142 (51.5889, -69.1986) -> (51.5684, -69.5641)
  line L143 (51.5684, -69.5641) -> (51.5226, -69.9334)
  line L144 (51.5226, -69.9334) -> (51.4553, -70.3055)
  line L145 (51.4553, -70.3055) -> (51.3687, -70.6798)
  line L146 (51.3687, -70.6798) -> (51.2642, -71.0558)
  line L147 (51.2642, -71.0558) -> (51.1428, -71.4331)
  line L148 (51.1428, -71.4331) -> (51.0051, -71.8111)
  line L149 (51.0051, -71.8111) -> (50.0112, -71.9156)
  line L150 (50.0112, -71.9156) -> (49.7979, -71.5744)
  line L151 (49.7979, -71.5744) -> (49.6007, -71.2307)
  line L152 (49.6007, -71.2307) -> (49.4203, -70.8846)
  line L153 (49.4203, -70.8846) -> (49.2578, -70.5365)
  line L154 (49.2578, -70.5365) -> (49.1146, -70.1864)
  line L155 (49.1146, -70.1864) -> (48.993, -69.8347)
  line L156 (48.993, -69.8347) -> (48.897, -69.4815)
  line L157 (48.897, -69.4815) -> (48.8387, -69.1264)
  line L158 (48.8387, -69.1264) -> (48.8181, -68.6088)
  line L159 (48.8181, -68.6088) -> (47.1819, -68.6088)
  line L160 (47.1819, -68.6088) -> (47.1613, -69.1264)
  line L161 (47.1613, -69.1264) -> (47.103, -69.4815)
  line L162 (47.103, -69.4815) -> (47.007, -69.8347)
  line L163 (47.007, -69.8347) -> (46.8854, -70.1864)
  line L164 (46.8854, -70.1864) -> (46.7422, -70.5365)
  line L165 (46.7422, -70.5365) -> (46.5797, -70.8846)
  line L166 (46.5797, -70.8846) -> (46.3993, -71.2307)
  line L167 (46.3993, -71.2307) -> (46.2021, -71.5744)
  line L168 (46.2021, -71.5744) -> (45.9888, -71.9156)
  line L169 (45.9888, -71.9156) -> (44.9949, -71.8111)
  line L170 (44.9949, -71.8111) -> (44.8572, -71.4331)
  line L171 (44.8572, -71.4331) -> (44.7358, -71.0558)
  line L172 (44.7358, -71.0558) -> (44.6313, -70.6798)
  line L173 (44.6313, -70.6798) -> (44.5447, -70.3055)
  line L174 (44.5447, -70.3055) -> (44.4774, -69.9334)
  line L175 (44.4774, -69.9334) -> (44.4316, -69.5641)
  line L176 (44.4316, -69.5641) -> (44.4111, -69.1986)
  line L177 (44.4111, -69.1986) -> (44.4279, -68.8392)
  line L178 (44.4279, -68.8392) -> (44.5155, -68.3285)
  line L179 (44.5155, -68.3285) -> (42.9149, -67.9883)
  line L180 (42.9149, -67.9883) -> (42.7872, -68.4904)
  line L181 (42.7872, -68.4904) -> (42.6564, -68.8256)
  line L182 (42.6564, -68.8256) -> (42.489, -69.1512)
  line L183 (42.489, -69.1512) -> (42.297, -69.4699)
  line L184 (42.297, -69.4699) -> (42.0841, -69.7825)
  line L185 (42.0841, -69.7825) -> (41.8527, -70.0892)
  line L186 (41.8527, -70.0892) -> (41.6043, -70.3902)
  line L187 (41.6043, -70.3902) -> (41.34, -70.6855)
  line L188 (41.34, -70.6855) -> (41.0604, -70.9748)
  line L189 (41.0604, -70.9748) -> (40.11, -70.666)
  line L190 (40.11, -70.666) -> (40.0539, -70.2676)
  line L191 (40.0539, -70.2676) -> (40.0136, -69.8734)
  line L192 (40.0136, -69.8734) -> (39.9895, -69.4838)
  line L193 (39.9895, -69.4838) -> (39.9826, -69.0997)
  line L194 (39.9826, -69.0997) -> (39.9942, -68.7217)
  line L195 (39.9942, -68.7217) -> (40.0261, -68.3509)
  line L196 (40.0261, -68.3509) -> (40.0821, -67.9891)
  line L197 (40.0821, -67.9891) -> (40.1733, -67.6411)
  line L198 (40.1733, -67.6411) -> (40.3651, -67.1598)
  line L199 (40.3651, -67.1598) -> (38.8703, -66.4943)
  line L200 (38.8703, -66.4943) -> (38.6409, -66.9588)
  line L201 (38.6409, -66.9588) -> (38.4433, -67.2595)
  line L202 (38.4433, -67.2595) -> (38.2119, -67.5432)
  line L203 (38.2119, -67.5432) -> (37.9577, -67.815)
  line L204 (37.9577, -67.815) -> (37.6846, -68.0765)
  line L205 (37.6846, -68.0765) -> (37.3945, -68.3284)
  line L206 (37.3945, -68.3284) -> (37.0889, -68.5712)
  line L207 (37.0889, -68.5712) -> (36.7689, -68.805)
  line L208 (36.7689, -68.805) -> (36.4353, -69.0299)
  line L209 (36.4353, -69.0299) -> (35.5699, -68.5303)
  line L210 (35.5699, -68.5303) -> (35.5979, -68.1289)
  line L211 (35.5979, -68.1289) -> (35.6403, -67.7349)
  line L212 (35.6403, -67.7349) -> (35.6978, -67.3489)
  line L213 (35.6978, -67.3489) -> (35.771, -66.9717)
  line L214 (35.771, -66.9717) -> (35.8608, -66.6043)
  line L215 (35.8608, -66.6043) -> (35.9692, -66.2483)
  line L216 (35.9692, -66.2483) -> (36.0992, -65.9061)
  line L217 (36.0992, -65.9061) -> (36.2607, -65.5846)
  line L218 (36.2607, -65.5846) -> (36.5484, -65.1537)
  line L219 (36.5484, -65.1537) -> (35.2246, -64.192)
  line L220 (35.2246, -64.192) -> (34.9037, -64.5987)
  line L221 (34.9037, -64.5987) -> (34.6478, -64.8517)
  line L222 (34.6478, -64.8517) -> (34.3625, -65.081)
  line L223 (34.3625, -65.081) -> (34.0574, -65.2941)
  line L224 (34.0574, -65.2941) -> (33.7358, -65.4931)
  line L225 (33.7358, -65.4931) -> (33.3997, -65.6792)
  line L226 (33.3997, -65.6792) -> (33.0503, -65.8531)
  line L227 (33.0503, -65.8531) -> (32.6887, -66.0153)
  line L228 (32.6887, -66.0153) -> (32.3157, -66.166)
  line L229 (32.3157, -66.166) -> (31.573, -65.4973)
  line L230 (31.573, -65.4973) -> (31.6838, -65.1105)
  line L231 (31.6838, -65.1105) -> (31.8073, -64.7339)
  line L232 (31.8073, -64.7339) -> (31.9438, -64.3683)
  line L233 (31.9438, -64.3683) -> (32.0938, -64.0146)
  line L234 (32.0938, -64.0146) -> (32.2581, -63.6739)
  line L235 (32.2581, -63.6739) -> (32.438, -63.3482)
  line L236 (32.438, -63.3482) -> (32.6363, -63.0405)
  line L237 (32.6363, -63.0405) -> (32.8612, -62.7596)
  line L238 (32.8612, -62.7596) -> (33.2321, -62.398)
  line L239 (33.2321, -62.398) -> (32.1373, -61.182)
  line L240 (32.1373, -61.182) -> (31.7388, -61.5131)
  line L241 (31.7388, -61.5131) -> (31.436, -61.7073)
  line L242 (31.436, -61.7073) -> (31.1092, -61.8724)
  line L243 (31.1092, -61.8724) -> (30.7665, -62.0173)
  line L244 (30.7665, -62.0173) -> (30.4105, -62.1451)
  line L245 (30.4105, -62.1451) -> (30.043, -62.2573)
  line L246 (30.043, -62.2573) -> (29.6651, -62.3548)
  line L247 (29.6651, -62.3548) -> (29.2777, -62.4382)
  line L248 (29.2777, -62.4382) -> (28.8815, -62.508)
  line L249 (28.8815, -62.508) -> (28.2941, -61.6995)
  line L250 (28.2941, -61.6995) -> (28.4829, -61.3443)
  line L251 (28.4829, -61.3443) -> (28.682, -61.0016)
  line L252 (28.682, -61.0016) -> (28.8915, -60.6723)
  line L253 (28.8915, -60.6723) -> (29.1117, -60.3575)
  line L254 (29.1117, -60.3575) -> (29.3433, -60.0585)
  line L255 (29.3433, -60.0585) -> (29.587, -59.7773)
  line L256 (29.587, -59.7773) -> (29.845, -59.5175)
  line L257 (29.845, -59.5175) -> (30.1233, -59.2895)
  line L258 (30.1233, -59.2895) -> (30.5614, -59.0129)
  line L259 (30.5614, -59.0129) -> (29.7432, -57.5959)
  line L260 (29.7432, -57.5959) -> (29.2846, -57.8369)
  line L261 (29.2846, -57.8369) -> (28.948, -57.9639)
  line L262 (28.948, -57.9639) -> (28.5941, -58.0575)
  line L263 (28.5941, -58.0575) -> (28.2287, -58.128)
  line L264 (28.2287, -58.128) -> (27.854, -58.179)
  line L265 (27.854, -58.179) -> (27.4712, -58.2123)
  line L266 (27.4712, -58.2123) -> (27.0813, -58.2291)
  line L267 (27.0813, -58.2291) -> (26.685, -58.2302)
  line L268 (26.685, -58.2302) -> (26.2829, -58.216)
  line L269 (26.2829, -58.216) -> (25.8764, -57.3031)
  line L270 (25.8764, -57.3031) -> (26.135, -56.9948)
  line L271 (26.135, -56.9948) -> (26.401, -56.701)
  line L272 (26.401, -56.701) -> (26.6743, -56.4225)
  line L273 (26.6743, -56.4225) -> (26.9552, -56.1604)
  line L274 (26.9552, -56.1604) -> (27.2439, -55.916)
  line L275 (27.2439, -55.916) -> (27.5408, -55.6917)
  line L276 (27.5408, -55.6917) -> (27.8471, -55.4912)
  line L277 (27.8471, -55.4912) -> (28.1667, -55.3261)
  line L278 (28.1667, -55.3261) -> (28.6527, -55.1466)
  line L279 (28.6527, -55.1466) -> (28.1471, -53.5904)
  line L280 (28.1471, -53.5904) -> (27.6484, -53.7308)
  line L281 (27.6484, -53.7308) -> (27.2927, -53.7851)
  line L282 (27.2927, -53.7851) -> (26.9271, -53.803)
  line L283 (26.9271, -53.803) -> (26.555, -53.796)
  line L284 (26.555, -53.796) -> (26.1779, -53.7679)
  line L285 (26.1779, -53.7679) -> (25.7965, -53.7209)
  line L286 (25.7965, -53.7209) -> (25.4117, -53.6563)
  line L287 (25.4117, -53.6563) -> (25.0238, -53.575)
  line L288 (25.0238, -53.575) -> (24.6334, -53.4776)
  line L289 (24.6334, -53.4776) -> (24.4257, -52.5)
  line L290 (24.4257, -52.5) -> (24.7427, -52.2523)
  line L291 (24.7427, -52.2523) -> (25.0639, -52.0202)
  line L292 (25.0639, -52.0202) -> (25.3892, -51.8046)
  line L293 (25.3892, -51.8046) -> (25.7185, -51.6066)
  line L294 (25.7185, -51.6066) -> (26.0516, -51.4276)
  line L295 (26.0516, -51.4276) -> (26.3887, -51.2699)
  line L296 (26.3887, -51.2699) -> (26.73, -51.1375)
  line L297 (26.73, -51.1375) -> (27.077, -51.0424)
  line L298 (27.077, -51.0424) -> (27.5896, -50.9679)
  line L299 (27.5896, -50.9679) -> (27.4186, -49.3405)
  line L300 (27.4186, -49.3405) -> (26.9016, -49.3742)
  line L301 (26.9016, -49.3742) -> (26.5424, -49.3534)
  line L302 (26.5424, -49.3534) -> (26.1811, -49.2948)
  line L303 (26.1811, -49.2948) -> (25.8186, -49.2106)
  line L304 (25.8186, -49.2106) -> (25.4555, -49.1048)
  line L305 (25.4555, -49.1048) -> (25.0923, -48.9796)
  line L306 (25.0923, -48.9796) -> (24.7293, -48.8363)
  line L307 (24.7293, -48.8363) -> (24.3668, -48.6761)
  line L308 (24.3668, -48.6761) -> (24.0052, -48.4997)
  line L309 (24.0052, -48.4997) -> (24.0052, -47.5003)
  line L310 (24.0052, -47.5003) -> (24.3668, -47.3239)
  line L311 (24.3668, -47.3239) -> (24.7293, -47.1637)
  line L312 (24.7293, -47.1637) -> (25.0923, -47.0204)
  line L313 (25.0923, -47.0204) -> (25.4555, -46.8952)
  line L314 (25.4555, -46.8952) -> (25.8186, -46.7894)
  line L315 (25.8186, -46.7894) -> (26.1811, -46.7052)
  line L316 (26.1811, -46.7052) -> (26.5424, -46.6466)
  line L317 (26.5424, -46.6466) -> (26.9016, -46.6258)
  line L318 (26.9016, -46.6258) -> (27.4186, -46.6595)
  line L319 (27.4186, -46.6595) -> (27.5896, -45.0321)
  line L320 (27.5896, -45.0321) -> (27.077, -44.9576)
  line L321 (27.077, -44.9576) -> (26.73, -44.8625)
  line L322 (26.73, -44.8625) -> (26.3887, -44.7301)
  line L323 (26.3887, -44.7301) -> (26.0516, -44.5724)
  line L324 (26.0516, -44.5724) -> (25.7185, -44.3934)
  line L325 (25.7185, -44.3934) -> (25.3892, -44.1954)
  line L326 (25.3892, -44.1954) -> (25.0639, -43.9798)
  line L327 (25.0639, -43.9798) -> (24.7427, -43.7477)
  line L328 (24.7427, -43.7477) -> (24.4257, -43.5)
  line L329 (24.4257, -43.5) -> (24.6334, -42.5224)
  line L330 (24.6334, -42.5224) -> (25.0238, -42.425)
  line L331 (25.0238, -42.425) -> (25.4117, -42.3437)
  line L332 (25.4117, -42.3437) -> (25.7965, -42.2791)
  line L333 (25.7965, -42.2791) -> (26.1779, -42.2321)
  line L334 (26.1779, -42.2321) -> (26.555, -42.204)
  line L335 (26.555, -42.204) -> (26.9271, -42.197)
  line L336 (26.9271, -42.197) -> (27.2927, -42.2149)
  line L337 (27.2927, -42.2149) -> (27.6484, -42.2692)
  line L338 (27.6484, -42.2692) -> (28.1471, -42.4096)
  line L339 (28.1471, -42.4096) -> (28.6527, -40.8534)
  line L340 (28.6527, -40.8534) -> (28.1667, -40.6739)
  line L341 (28.1667, -40.6739) -> (27.8471, -40.5088)
  line L342 (27.8471, -40.5088) -> (27.5408, -40.3083)
  line L343 (27.5408, -40.3083) -> (27.2439, -40.084)
  line L344 (27.2439, -40.084) -> (26.9552, -39.8396)
  line L345 (26.9552, -39.8396) -> (26.6743, -39.5775)
  line L346 (26.6743, -39.5775) -> (26.401, -39.299)
  line L347 (26.401, -39.299) -> (26.135, -39.0052)
  line L348 (26.135, -39.0052) -> (25.8764, -38.6969)
  line L349 (25.8764, -38.6969) -> (26.2829, -37.784)
  line L350 (26.2829, -37.784) -> (26.685, -37.7698)
  line L351 (26.685, -37.7698) -> (27.0813, -37.7709)
  line L352 (27.0813, -37.7709) -> (27.4712, -37.7877)
  line L353 (27.4712, -37.7877) -> (27.854, -37.821)
  line L354 (27.854, -37.821) -> (28.2287, -37.872)
  line L355 (28.2287, -37.872) -> (28.5941, -37.9425)
  line L356 (28.5941, -37.9425) -> (28.948, -38.0361)
  line L357 (28.948, -38.0361) -> (29.2846, -38.1631)
  line L358 (29.2846, -38.1631) -> (29.7432, -38.4041)
  line L359 (29.7432, -38.4041) -> (30.5614, -36.9871)
  line L360 (30.5614, -36.9871) -> (30.1233, -36.7105)
  line L361 (30.1233, -36.7105) -> (29.845, -36.4825)
  line L362 (29.845, -36.4825) -> (29.587, -36.2227)
  line L363 (29.587, -36.2227) -> (29.3433, -35.9415)
  line L364 (29.3433, -35.9415) -> (29.1117, -35.6425)
  line L365 (29.1117, -35.6425) -> (28.8915, -35.3277)
  line L366 (28.8915, -35.3277) -> (28.682, -34.9984)
  line L367 (28.682, -34.9984) -> (28.4829, -34.6557)
  line L368 (28.4829, -34.6557) -> (28.2941, -34.3005)
  line L369 (28.2941, -34.3005) -> (28.8815, -33.492)
  line L370 (28.8815, -33.492) -> (29.2777, -33.5618)
  line L371 (29.2777, -33.5618) -> (29.6651, -33.6452)
  line L372 (29.6651, -33.6452) -> (30.043, -33.7427)
  line L373 (30.043, -33.7427) -> (30.4105, -33.8549)
  line L374 (30.4105, -33.8549) -> (30.7665, -33.9827)
  line L375 (30.7665, -33.9827) -> (31.1092, -34.1276)
  line L376 (31.1092, -34.1276) -> (31.436, -34.2927)
  line L377 (31.436, -34.2927) -> (31.7388, -34.4869)
  line L378 (31.7388, -34.4869) -> (32.1373, -34.818)
  line L379 (32.1373, -34.818) -> (33.2321, -33.602)
  line L380 (33.2321, -33.602) -> (32.8612, -33.2404)
  line L381 (32.8612, -33.2404) -> (32.6363, -32.9595)
  line L382 (32.6363, -32.9595) -> (32.438, -32.6518)
  line L383 (32.438, -32.6518) -> (32.2581, -32.3261)
  line L384 (32.2581, -32.3261) -> (32.0938, -31.9854)
  line L385 (32.0938, -31.9854) -> (31.9438, -31.6317)
  line L386 (31.9438, -31.6317) -> (31.8073, -31.2661)
  line L387 (31.8073, -31.2661) -> (31.6838, -30.8895)
  line L388 (31.6838, -30.8895) -> (31.573, -30.5027)
  line L389 (31.573, -30.5027) -> (32.3157, -29.834)
  line L390 (32.3157, -29.834) -> (32.6887, -29.9847)
  line L391 (32.6887, -29.9847) -> (33.0503, -30.1469)
  line L392 (33.0503, -30.1469) -> (33.3997, -30.3208)
  line L393 (33.3997, -30.3208) -> (33.7358, -30.5069)
  line L394 (33.7358, -30.5069) -> (34.0574, -30.7059)
  line L395 (34.0574, -30.7059) -> (34.3625, -30.919)
  line L396 (34.3625, -30.919) -> (34.6478, -31.1483)
  line L397 (34.6478, -31.1483) -> (34.9037, -31.4013)
  line L398 (34.9037, -31.4013) -> (35.2246, -31.808)
  line L399 (35.2246, -31.808) -> (36.5484, -30.8463)
  line L400 (36.5484, -30.8463) -> (36.2607, -30.4154)
  line L401 (36.2607, -30.4154) -> (36.0992, -30.0939)
  line L402 (36.0992, -30.0939) -> (35.9692, -29.7517)
  line L403 (35.9692, -29.7517) -> (35.8608, -29.3957)
  line L404 (35.8608, -29.3957) -> (35.771, -29.0283)
  line L405 (35.771, -29.0283) -> (35.6978, -28.6511)
  line L406 (35.6978, -28.6511) -> (35.6403, -28.2651)
  line L407 (35.6403, -28.2651) -> (35.5979, -27.8711)
  line L408 (35.5979, -27.8711) -> (35.5699, -27.4697)
  line L409 (35.5699, -27.4697) -> (36.4353, -26.9701)
  line L410 (36.4353, -26.9701) -> (36.7689, -27.195)
  line L411 (36.7689, -27.195) -> (37.0889, -27.4288)
  line L412 (37.0889, -27.4288) -> (37.3945, -27.6716)
  line L413 (37.3945, -27.6716) -> (37.6846, -27.9235)
  line L414 (37.6846, -27.9235) -> (37.9577, -28.185)
  line L415 (37.9577, -28.185) -> (38.2119, -28.4568)
  line L416 (38.2119, -28.4568) -> (38.4433, -28.7405)
  line L417 (38.4433, -28.7405) -> (38.6409, -29.0412)
  line L418 (38.6409, -29.0412) -> (38.8703, -29.5057)
  line L419 (38.8703, -29.5057) -> (40.3651, -28.8402)
  line L420 (40.3651, -28.8402) -> (40.1733, -28.3589)
  line L421 (40.1733, -28.3589) -> (40.0821, -28.0109)
  line L422 (40.0821, -28.0109) -> (40.0261, -27.6491)
  line L423 (40.0261, -27.6491) -> (39.9942, -27.2783)
  line L424 (39.9942, -27.2783) -> (39.9826, -26.9003)
  line L425 (39.9826, -26.9003) -> (39.9895, -26.5162)
  line L426 (39.9895, -26.5162) -> (40.0136, -26.1266)
  line L427 (40.0136, -26.1266) -> (40.0539, -25.7324)
  line L428 (40.0539, -25.7324) -> (40.11, -25.334)
  line L429 (40.11, -25.334) -> (41.0604, -25.0252)
  line L430 (41.0604, -25.0252) -> (41.34, -25.3145)
  line L431 (41.34, -25.3145) -> (41.6043, -25.6098)
  line L432 (41.6043, -25.6098) -> (41.8527, -25.9108)
  line L433 (41.8527, -25.9108) -> (42.0841, -26.2175)
  line L434 (42.0841, -26.2175) -> (42.297, -26.5301)
  line L435 (42.297, -26.5301) -> (42.489, -26.8488)
  line L436 (42.489, -26.8488) -> (42.6564, -27.1744)
  line L437 (42.6564, -27.1744) -> (42.7872, -27.5096)
  line L438 (42.7872, -27.5096) -> (42.9149, -28.0117)